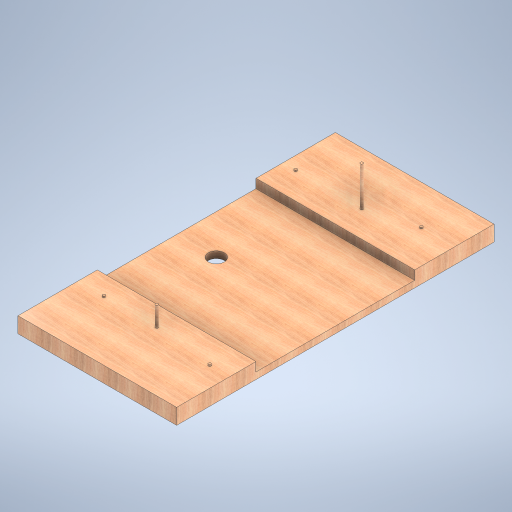
# Autodesk Inventor part: BasePlate
Saved by Autodesk Inventor 2023 (Build 270158000, 158)
## iProperties
Created: 2024-03-28
Part Number: BasePlate
Material: Wood (Birch)
Document SubType Name: Modeling
Designer: BenFr
Density: 0.55 g/cm^3
Appearance: Birch - Natural Polished
Author: BenFr
Autodesk Inventor part; units mm, degrees
ref_plane "YZ Plane" through (0, 0, 0) normal (1, 0, 0) x (0, 1, 0)
ref_plane "XZ Plane" through (0, 0, 0) normal (0, 1, 0) x (-1, 0, 0)
ref_plane "XY Plane" through (0, 0, 0) normal (0, 0, 1) x (1, 0, 0)
sketch "Sketch1" plane through (0, 0, 0) normal (0, 1, 0) x (-1, 0, 0)
  line L0 (-600, 600) -> (600, 600)
  line L1 (600, 600) -> (600, -600)
  line L2 (600, -600) -> (-600, -600)
  line L3 (-600, -600) -> (-600, 600)
  line L4 (-600, 600) -> (600, -600) construction
  line L5 (600, 600) -> (-600, -600) construction
  line L6 (600, -600) -> (-600, -600)
  line L7 (-600, -600) -> (-600, -1200)
  line L8 (-600, -1200) -> (600, -1200)
  line L9 (600, -1200) -> (600, -600)
  line L10 (600, 600) -> (-600, 600)
  line L11 (-600, 600) -> (-600, 1200)
  line L12 (-600, 1200) -> (600, 1200)
  line L13 (600, 1200) -> (600, 600)
  point P0 (0, 0)
  dimension "d0" = 1200
  dimension "d1" = 1200
  dimension "d2" = 1200
  dimension "d3" = 600
  dimension "d4" = 1200
  dimension "d5" = 600
  constraints: 28 end point, 6 parallel, 3 horizontal, 3 perpendicular, 2 midpoint
  measures "d0" distance of L1.end L2.end
  measures "d1" distance of L0.end L1.end
  measures "d2" distance of L8.end L7.end
  measures "d3" distance of L7.end L6.end
  measures "d4" distance of L11.end L12.end
  measures "d5" distance of L10.end L11.end
extrude "Extrusion1" add sketch "Sketch1" along normal blind 68 contours L11 L12 L13 L0 | L2 L9 L8 L7
sketch "Sketch2" plane through (0, 0, 0) normal (0, -1, 0) x (1, 0, 0)
  line L0 (-600, 1200) -> (600, 1200) projected
  line L1 (600, -1200) -> (-600, -1200) projected
  line L2 (600, 1200) -> (-600, 1200)
  line L3 (-600, 1200) -> (-600, -1200)
  line L4 (-600, -1200) -> (600, -1200)
  line L5 (600, -1200) -> (600, 1200)
  point P0 (0, 0)
  constraints: 8 end point, 2 parallel, 1 horizontal, 1 perpendicular
extrude "Extrusion2" add sketch "Sketch2" along normal blind 50
sketch "Sketch3" plane through (0, 0, 0) normal (0, 1, 0) x (1, 0, 0)
  circle A0 centre (-300, 0) radius 60
  point P0 (0, 0)
  dimension "d10" = 120
  constraints: 1 centre point
  measures "d10" diameter of A0
extrude "Extrusion3" cut sketch "Sketch3" against normal blind 50
sketch "Sketch4" plane through (0, 68, 0) normal (0, 1, 0) x (1, 0, 0)
  circle A0 centre (0, 800) radius 10
  point P0 (0, 0)
  dimension "d13" = 20
  constraints: 1 centre point
  measures "d13" diameter of A0
sketch "Sketch5" plane through (0, 68, 0) normal (0, 1, 0) x (1, 0, 0)
  circle A0 centre (0, -750) radius 10
  point P0 (0, 0)
  dimension "d14" = 20
  constraints: 1 centre point
  measures "d14" diameter of A0
extrude "Extrusion4" add sketch "Sketch4" along normal blind 300
extrude "Extrusion5" add sketch "Sketch5" along normal blind 150
sketch "Sketch6" plane through (0, 68, 0) normal (0, 1, 0) x (1, 0, 0)
  circle A0 centre (350, 900) radius 10
  circle A1 centre (-500, 800) radius 10
  point P0 (0, 0)
  dimension "d19" = 20
  dimension "d20" = 20
  constraints: 2 centre point
  measures "d19" diameter of A0
  measures "d20" diameter of A1
extrude "Extrusion6" add sketch "Sketch6" along normal blind 10
sketch "Sketch7" plane through (0, 68, 0) normal (0, 1, 0) x (1, 0, 0)
  circle A0 centre (450, -800) radius 10
  circle A1 centre (-400, -750) radius 10
  point P0 (0, 0)
  dimension "d23" = 20
  dimension "d24" = 20
  constraints: 2 centre point
  measures "d23" diameter of A0
  measures "d24" diameter of A1
extrude "Extrusion7" add sketch "Sketch7" along normal blind 10
body "Solid1"
